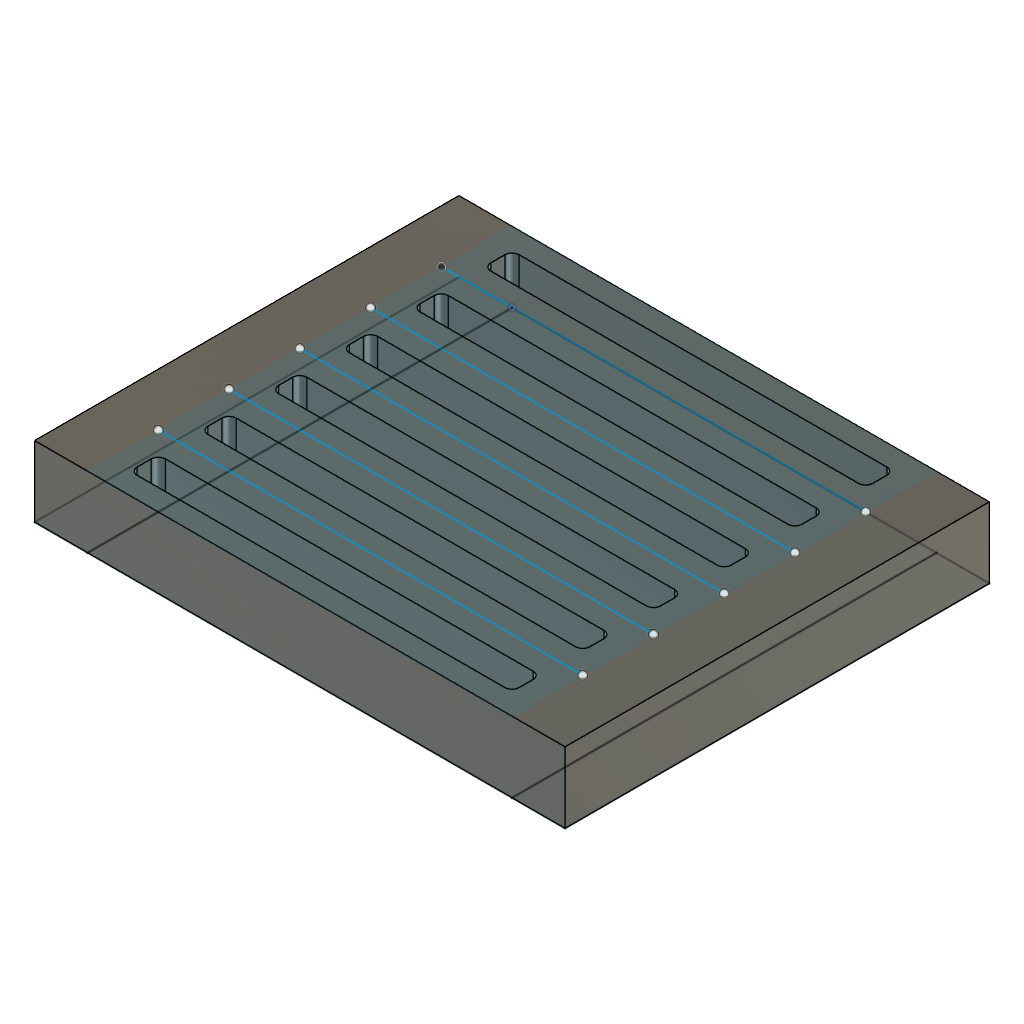
Lateral_modificado (Autodesk Fusion 360 archive; units mm, degrees)
design "Lateral_modificado"
part number: 2026-10-18-20-49-54-475
Autodesk Fusion 360 part; units mm, degrees
sketch "Boceto1" plane through (0, 0, 0) normal (0, 0, 1) x (1, 0, 0)
  line L0 (0, 0) -> (60, 0)
  line L1 (60, 0) -> (60, -60)
  line L2 (60, -60) -> (0, -60)
  line L3 (0, -60) -> (0, 0)
  line L4 (0, 0) -> (-7.5, 0)
  line L5 (-7.5, 0) -> (-7.5, -60)
  line L6 (-7.5, -60) -> (0, -60)
  line L7 (0, -60) -> (0, 0)
  line L8 (60, 0) -> (67.5, 0)
  line L9 (67.5, 0) -> (67.5, -60)
  line L10 (67.5, -60) -> (60, -60)
  line L11 (60, -60) -> (60, 0)
  dimension "d1" = 60
  dimension "d2" = 60
  dimension "d25" = 60
  dimension "d26" = 7.5
  dimension "d29" = 60
  dimension "d30" = 7.5
  constraint horizontal L0
  constraint vertical L1
  constraint horizontal L2
  constraint vertical L3
  constraint coincident L0.start L3.end
  constraint horizontal L4
  constraint vertical L5
  constraint horizontal L6
  constraint vertical L7
  constraint horizontal L8
  constraint vertical L9
  constraint horizontal L10
  constraint vertical L11
  measures "d1" distance of L0.start L0.end
  measures "d2" distance of L0.start L2.end
  measures "d25" distance of L0.start L2.end
  measures "d26" distance of L0.start L4.end
  measures "d29" distance of L0.end L1.end
  measures "d30" distance of L0.end L8.end
extrude "Extruir1" add sketch "Boceto1" along normal blind 10 contours L0 L1 L2 L3 L7 L11 makes body 1
sketch "Boceto2" plane through (0, 0, 10) normal (0, 0, 1) x (-1, 0, 0)
  line L0 (0, 60) -> (-60, 60)
  line L1 (-60, 60) -> (-60, 0)
  line L2 (-60, 0) -> (0, 0)
  line L3 (0, 0) -> (0, 60)
  line L4 (0, 10) -> (-60, 10)
  line L5 (0, 20) -> (-60, 20)
  line L6 (0, 30) -> (-60, 30)
  line L7 (0, 40) -> (-60, 40)
  line L8 (0, 50) -> (-60, 50)
  dimension "d5" = 60
  dimension "d6" = 10
  dimension "d7" = 10
  dimension "d8" = 10
  dimension "d9" = 10
  constraint coincident L3 L4.start
  constraint perpendicular L3 L4
  measures "d5" distance of L4.start L4.end
sketch "Boceto3" plane through (0, 0, 10) normal (0, 0, 1) x (-1, 0, 0)
  line L0 (0, 0) -> (-3, 0)
  line L1 (-3, 3) -> (0, 3)
  line L2 (0, 3) -> (0, 0)
  line L3 (-4, 3) -> (-56, 3)
  line L4 (-57, 4) -> (-57, 6)
  line L5 (-56, 7) -> (-4, 7)
  line L6 (-3, 6) -> (-3, 4)
  arc A0 (-4, 3) -> (-3, 4) centre (-4, 4) ccw
  arc A1 (-3, 6) -> (-4, 7) centre (-4, 6) ccw
  arc A2 (-56, 7) -> (-57, 6) centre (-56, 6) ccw
  arc A3 (-57, 4) -> (-56, 3) centre (-56, 4) ccw
  arc A4 (-3, 6) -> (-4, 7) centre (-4, 6) ccw
  line L7 (-56, 7) -> (-4, 7)
  arc A5 (-56, 7) -> (-57, 6) centre (-56, 6) ccw
  line L8 (-57, 4) -> (-57, 6)
  arc A6 (-57, 4) -> (-56, 3) centre (-56, 4) ccw
  line L9 (-4, 3) -> (-56, 3)
  arc A7 (-4, 3) -> (-3, 4) centre (-4, 4) ccw
  line L10 (-3, 6) -> (-3, 4)
  arc A8 (-3, 6) -> (-4, 7) centre (-4, 6) ccw
  line L11 (-56, 7) -> (-4, 7)
  arc A9 (-56, 7) -> (-57, 6) centre (-56, 6) ccw
  line L12 (-57, 4) -> (-57, 6)
  arc A10 (-57, 4) -> (-56, 3) centre (-56, 4) ccw
  line L13 (-4, 3) -> (-56, 3)
  arc A11 (-4, 3) -> (-3, 4) centre (-4, 4) ccw
  line L14 (-3, 6) -> (-3, 4)
  arc A12 (-3, 6) -> (-4, 7) centre (-4, 6) ccw
  line L15 (-56, 7) -> (-4, 7)
  arc A13 (-56, 7) -> (-57, 6) centre (-56, 6) ccw
  line L16 (-57, 4) -> (-57, 6)
  arc A14 (-57, 4) -> (-56, 3) centre (-56, 4) ccw
  line L17 (-4, 3) -> (-56, 3)
  arc A15 (-4, 3) -> (-3, 4) centre (-4, 4) ccw
  line L18 (-3, 6) -> (-3, 4)
  line L19 (0, 10) -> (-60, 10)
  line L20 (-56, 13) -> (-4, 13)
  line L21 (-56, 13) -> (-4, 13)
  line L22 (-56, 13) -> (-4, 13)
  line L23 (-56, 13) -> (-4, 13)
  arc A16 (-4, 13) -> (-3, 14) centre (-4, 14) ccw
  line L24 (-3, 14) -> (-3, 16)
  line L25 (-3, 14) -> (-3, 16)
  arc A17 (-4, 13) -> (-3, 14) centre (-4, 14) ccw
  line L26 (-3, 14) -> (-3, 16)
  arc A18 (-4, 13) -> (-3, 14) centre (-4, 14) ccw
  line L27 (-3, 14) -> (-3, 16)
  arc A19 (-4, 13) -> (-3, 14) centre (-4, 14) ccw
  arc A20 (-3, 16) -> (-4, 17) centre (-4, 16) ccw
  arc A21 (-3, 16) -> (-4, 17) centre (-4, 16) ccw
  arc A22 (-3, 16) -> (-4, 17) centre (-4, 16) ccw
  arc A23 (-3, 16) -> (-4, 17) centre (-4, 16) ccw
  line L28 (-57, 16) -> (-57, 14)
  arc A24 (-57, 14) -> (-56, 13) centre (-56, 14) ccw
  arc A25 (-56, 17) -> (-57, 16) centre (-56, 16) ccw
  arc A26 (-57, 14) -> (-56, 13) centre (-56, 14) ccw
  arc A27 (-57, 14) -> (-56, 13) centre (-56, 14) ccw
  line L29 (-57, 16) -> (-57, 14)
  arc A28 (-56, 17) -> (-57, 16) centre (-56, 16) ccw
  arc A29 (-57, 14) -> (-56, 13) centre (-56, 14) ccw
  arc A30 (-56, 17) -> (-57, 16) centre (-56, 16) ccw
  line L30 (-57, 16) -> (-57, 14)
  arc A31 (-56, 17) -> (-57, 16) centre (-56, 16) ccw
  line L31 (-57, 16) -> (-57, 14)
  line L32 (-4, 17) -> (-56, 17)
  line L33 (0, 20) -> (-60, 20)
  line L34 (-57, 36) -> (-57, 34)
  line L35 (-3, 34) -> (-3, 36)
  line L36 (-4, 37) -> (-56, 37)
  arc A32 (-57, 34) -> (-56, 33) centre (-56, 34) ccw
  arc A33 (-4, 33) -> (-3, 34) centre (-4, 34) ccw
  arc A34 (-56, 37) -> (-57, 36) centre (-56, 36) ccw
  arc A35 (-4, 33) -> (-3, 34) centre (-4, 34) ccw
  arc A36 (-56, 37) -> (-57, 36) centre (-56, 36) ccw
  arc A37 (-56, 37) -> (-57, 36) centre (-56, 36) ccw
  arc A38 (-3, 36) -> (-4, 37) centre (-4, 36) ccw
  line L37 (-56, 33) -> (-4, 33)
  arc A39 (-4, 33) -> (-3, 34) centre (-4, 34) ccw
  arc A40 (-4, 33) -> (-3, 34) centre (-4, 34) ccw
  line L38 (-4, 37) -> (-56, 37)
  arc A41 (-57, 34) -> (-56, 33) centre (-56, 34) ccw
  arc A42 (-3, 36) -> (-4, 37) centre (-4, 36) ccw
  line L39 (-3, 34) -> (-3, 36)
  line L40 (-4, 37) -> (-56, 37)
  line L41 (-3, 34) -> (-3, 36)
  line L42 (-3, 34) -> (-3, 36)
  arc A43 (-57, 34) -> (-56, 33) centre (-56, 34) ccw
  line L43 (-56, 33) -> (-4, 33)
  line L44 (-57, 36) -> (-57, 34)
  arc A44 (-56, 37) -> (-57, 36) centre (-56, 36) ccw
  line L45 (-56, 33) -> (-4, 33)
  line L46 (-4, 37) -> (-56, 37)
  line L47 (-57, 36) -> (-57, 34)
  arc A45 (-3, 36) -> (-4, 37) centre (-4, 36) ccw
  line L48 (-56, 33) -> (-4, 33)
  arc A46 (-3, 36) -> (-4, 37) centre (-4, 36) ccw
  line L49 (-57, 36) -> (-57, 34)
  arc A47 (-57, 34) -> (-56, 33) centre (-56, 34) ccw
  line L50 (-56, 33) -> (-4, 33)
  line L51 (-56, 33) -> (-4, 33)
  arc A48 (-56, 37) -> (-57, 36) centre (-56, 36) ccw
  line L52 (-4, 37) -> (-56, 37)
  arc A49 (-3, 36) -> (-4, 37) centre (-4, 36) ccw
  line L53 (-57, 36) -> (-57, 34)
  arc A50 (-56, 37) -> (-57, 36) centre (-56, 36) ccw
  arc A51 (-4, 33) -> (-3, 34) centre (-4, 34) ccw
  arc A52 (-57, 34) -> (-56, 33) centre (-56, 34) ccw
  line L54 (-4, 37) -> (-56, 37)
  arc A53 (-4, 33) -> (-3, 34) centre (-4, 34) ccw
  line L55 (-3, 34) -> (-3, 36)
  line L56 (-3, 34) -> (-3, 36)
  arc A54 (-4, 33) -> (-3, 34) centre (-4, 34) ccw
  arc A55 (-3, 36) -> (-4, 37) centre (-4, 36) ccw
  line L57 (-56, 33) -> (-4, 33)
  arc A56 (-4, 33) -> (-3, 34) centre (-4, 34) ccw
  line L58 (-56, 33) -> (-4, 33)
  line L59 (-57, 36) -> (-57, 34)
  arc A57 (-57, 34) -> (-56, 33) centre (-56, 34) ccw
  arc A58 (-57, 34) -> (-56, 33) centre (-56, 34) ccw
  line L60 (-57, 36) -> (-57, 34)
  arc A59 (-56, 37) -> (-57, 36) centre (-56, 36) ccw
  line L61 (-3, 34) -> (-3, 36)
  line L62 (-4, 37) -> (-56, 37)
  line L63 (-3, 34) -> (-3, 36)
  arc A60 (-56, 37) -> (-57, 36) centre (-56, 36) ccw
  line L64 (-57, 36) -> (-57, 34)
  arc A61 (-57, 34) -> (-56, 33) centre (-56, 34) ccw
  arc A62 (-3, 36) -> (-4, 37) centre (-4, 36) ccw
  arc A63 (-3, 36) -> (-4, 37) centre (-4, 36) ccw
  line L65 (-4, 37) -> (-56, 37)
  line L66 (-3, 26) -> (-3, 24)
  arc A64 (-4, 23) -> (-3, 24) centre (-4, 24) ccw
  arc A65 (-3, 26) -> (-4, 27) centre (-4, 26) ccw
  line L67 (-57, 24) -> (-57, 26)
  arc A66 (-56, 27) -> (-57, 26) centre (-56, 26) ccw
  arc A67 (-56, 27) -> (-57, 26) centre (-56, 26) ccw
  arc A68 (-4, 23) -> (-3, 24) centre (-4, 24) ccw
  arc A69 (-3, 26) -> (-4, 27) centre (-4, 26) ccw
  arc A70 (-3, 26) -> (-4, 27) centre (-4, 26) ccw
  arc A71 (-4, 23) -> (-3, 24) centre (-4, 24) ccw
  arc A72 (-57, 24) -> (-56, 23) centre (-56, 24) ccw
  line L68 (-3, 26) -> (-3, 24)
  line L69 (-57, 24) -> (-57, 26)
  arc A73 (-56, 27) -> (-57, 26) centre (-56, 26) ccw
  arc A74 (-57, 24) -> (-56, 23) centre (-56, 24) ccw
  arc A75 (-56, 27) -> (-57, 26) centre (-56, 26) ccw
  arc A76 (-4, 23) -> (-3, 24) centre (-4, 24) ccw
  line L70 (-57, 24) -> (-57, 26)
  line L71 (-3, 26) -> (-3, 24)
  line L72 (-56, 27) -> (-4, 27)
  arc A77 (-57, 24) -> (-56, 23) centre (-56, 24) ccw
  line L73 (-56, 27) -> (-4, 27)
  line L74 (-4, 23) -> (-56, 23)
  arc A78 (-3, 26) -> (-4, 27) centre (-4, 26) ccw
  line L75 (-3, 26) -> (-3, 24)
  line L76 (-56, 27) -> (-4, 27)
  arc A79 (-57, 24) -> (-56, 23) centre (-56, 24) ccw
  line L77 (-57, 24) -> (-57, 26)
  line L78 (-56, 27) -> (-4, 27)
  line L79 (0, 40) -> (-60, 40)
  line L80 (-57, 44) -> (-57, 46)
  arc A80 (-3, 46) -> (-4, 47) centre (-4, 46) ccw
  arc A81 (-3, 46) -> (-4, 47) centre (-4, 46) ccw
  line L81 (-57, 44) -> (-57, 46)
  arc A82 (-3, 46) -> (-4, 47) centre (-4, 46) ccw
  line L82 (-57, 44) -> (-57, 46)
  arc A83 (-4, 43) -> (-3, 44) centre (-4, 44) ccw
  arc A84 (-4, 43) -> (-3, 44) centre (-4, 44) ccw
  line L83 (-57, 44) -> (-57, 46)
  arc A85 (-4, 43) -> (-3, 44) centre (-4, 44) ccw
  arc A86 (-3, 46) -> (-4, 47) centre (-4, 46) ccw
  arc A87 (-4, 43) -> (-3, 44) centre (-4, 44) ccw
  line L84 (-57, 44) -> (-57, 46)
  arc A88 (-3, 46) -> (-4, 47) centre (-4, 46) ccw
  arc A89 (-3, 46) -> (-4, 47) centre (-4, 46) ccw
  arc A90 (-4, 43) -> (-3, 44) centre (-4, 44) ccw
  arc A91 (-4, 43) -> (-3, 44) centre (-4, 44) ccw
  line L85 (-57, 44) -> (-57, 46)
  line L86 (-57, 44) -> (-57, 46)
  line L87 (-57, 44) -> (-57, 46)
  arc A92 (-4, 43) -> (-3, 44) centre (-4, 44) ccw
  arc A93 (-56, 47) -> (-57, 46) centre (-56, 46) ccw
  arc A94 (-57, 44) -> (-56, 43) centre (-56, 44) ccw
  arc A95 (-57, 44) -> (-56, 43) centre (-56, 44) ccw
  arc A96 (-56, 47) -> (-57, 46) centre (-56, 46) ccw
  arc A97 (-57, 44) -> (-56, 43) centre (-56, 44) ccw
  arc A98 (-56, 47) -> (-57, 46) centre (-56, 46) ccw
  arc A99 (-57, 44) -> (-56, 43) centre (-56, 44) ccw
  arc A100 (-56, 47) -> (-57, 46) centre (-56, 46) ccw
  arc A101 (-56, 47) -> (-57, 46) centre (-56, 46) ccw
  line L88 (-56, 47) -> (-4, 47)
  line L89 (-4, 43) -> (-56, 43)
  arc A102 (-4, 43) -> (-3, 44) centre (-4, 44) ccw
  line L90 (-3, 46) -> (-3, 44)
  line L91 (-4, 43) -> (-56, 43)
  line L92 (-56, 47) -> (-4, 47)
  line L93 (-4, 43) -> (-56, 43)
  line L94 (-3, 46) -> (-3, 44)
  line L95 (-56, 47) -> (-4, 47)
  line L96 (-56, 47) -> (-4, 47)
  line L97 (-56, 47) -> (-4, 47)
  line L98 (-3, 46) -> (-3, 44)
  line L99 (-4, 43) -> (-56, 43)
  line L100 (-56, 47) -> (-4, 47)
  line L101 (-56, 47) -> (-4, 47)
  line L102 (-4, 43) -> (-56, 43)
  line L103 (-3, 46) -> (-3, 44)
  line L104 (-4, 43) -> (-56, 43)
  arc A103 (-3, 46) -> (-4, 47) centre (-4, 46) ccw
  arc A104 (-3, 46) -> (-4, 47) centre (-4, 46) ccw
  line L105 (-3, 46) -> (-3, 44)
  line L106 (-3, 46) -> (-3, 44)
  line L107 (-56, 47) -> (-4, 47)
  line L108 (-4, 43) -> (-56, 43)
  line L109 (-3, 46) -> (-3, 44)
  line L110 (-3, 46) -> (-3, 44)
  line L111 (-4, 43) -> (-56, 43)
  arc A105 (-56, 47) -> (-57, 46) centre (-56, 46) ccw
  arc A106 (-57, 44) -> (-56, 43) centre (-56, 44) ccw
  arc A107 (-57, 44) -> (-56, 43) centre (-56, 44) ccw
  arc A108 (-56, 47) -> (-57, 46) centre (-56, 46) ccw
  arc A109 (-57, 44) -> (-56, 43) centre (-56, 44) ccw
  arc A110 (-57, 44) -> (-56, 43) centre (-56, 44) ccw
  arc A111 (-56, 47) -> (-57, 46) centre (-56, 46) ccw
  line L112 (0, 50) -> (-60, 50)
  line L113 (-3, 54) -> (-3, 56)
  line L114 (-57, 56) -> (-57, 54)
  line L115 (-57, 56) -> (-57, 54)
  line L116 (-3, 54) -> (-3, 56)
  line L117 (-57, 56) -> (-57, 54)
  line L118 (-3, 54) -> (-3, 56)
  line L119 (-57, 56) -> (-57, 54)
  line L120 (-3, 54) -> (-3, 56)
  line L121 (-3, 54) -> (-3, 56)
  line L122 (-3, 54) -> (-3, 56)
  line L123 (-3, 54) -> (-3, 56)
  line L124 (-3, 54) -> (-3, 56)
  line L125 (-56, 53) -> (-4, 53)
  arc A112 (-56, 57) -> (-57, 56) centre (-56, 56) ccw
  line L126 (-4, 57) -> (-56, 57)
  line L127 (-4, 57) -> (-56, 57)
  line L128 (-4, 57) -> (-56, 57)
  arc A113 (-56, 57) -> (-57, 56) centre (-56, 56) ccw
  line L129 (-4, 57) -> (-56, 57)
  line L130 (-56, 53) -> (-4, 53)
  line L131 (-56, 53) -> (-4, 53)
  arc A114 (-56, 57) -> (-57, 56) centre (-56, 56) ccw
  arc A115 (-56, 57) -> (-57, 56) centre (-56, 56) ccw
  line L132 (-56, 53) -> (-4, 53)
  arc A116 (-57, 54) -> (-56, 53) centre (-56, 54) ccw
  arc A117 (-57, 54) -> (-56, 53) centre (-56, 54) ccw
  arc A118 (-57, 54) -> (-56, 53) centre (-56, 54) ccw
  arc A119 (-57, 54) -> (-56, 53) centre (-56, 54) ccw
  arc A120 (-56, 57) -> (-57, 56) centre (-56, 56) ccw
  arc A121 (-57, 54) -> (-56, 53) centre (-56, 54) ccw
  line L133 (-4, 57) -> (-56, 57)
  line L134 (-4, 57) -> (-56, 57)
  arc A122 (-57, 54) -> (-56, 53) centre (-56, 54) ccw
  arc A123 (-4, 53) -> (-3, 54) centre (-4, 54) ccw
  arc A124 (-4, 53) -> (-3, 54) centre (-4, 54) ccw
  line L135 (-4, 57) -> (-56, 57)
  arc A125 (-3, 56) -> (-4, 57) centre (-4, 56) ccw
  arc A126 (-3, 56) -> (-4, 57) centre (-4, 56) ccw
  arc A127 (-4, 53) -> (-3, 54) centre (-4, 54) ccw
  line L136 (-56, 53) -> (-4, 53)
  arc A128 (-57, 54) -> (-56, 53) centre (-56, 54) ccw
  line L137 (-56, 53) -> (-4, 53)
  line L138 (-57, 56) -> (-57, 54)
  arc A129 (-3, 56) -> (-4, 57) centre (-4, 56) ccw
  arc A130 (-4, 53) -> (-3, 54) centre (-4, 54) ccw
  arc A131 (-3, 56) -> (-4, 57) centre (-4, 56) ccw
  arc A132 (-4, 53) -> (-3, 54) centre (-4, 54) ccw
  line L139 (-57, 56) -> (-57, 54)
  arc A133 (-4, 53) -> (-3, 54) centre (-4, 54) ccw
  arc A134 (-56, 57) -> (-57, 56) centre (-56, 56) ccw
  arc A135 (-3, 56) -> (-4, 57) centre (-4, 56) ccw
  line L140 (-57, 56) -> (-57, 54)
  arc A136 (-4, 53) -> (-3, 54) centre (-4, 54) ccw
  arc A137 (-4, 53) -> (-3, 54) centre (-4, 54) ccw
  line L141 (-56, 53) -> (-4, 53)
  line L142 (-4, 57) -> (-56, 57)
  line L143 (-57, 56) -> (-57, 54)
  arc A138 (-3, 56) -> (-4, 57) centre (-4, 56) ccw
  arc A139 (-3, 56) -> (-4, 57) centre (-4, 56) ccw
  arc A140 (-3, 56) -> (-4, 57) centre (-4, 56) ccw
  arc A141 (-56, 57) -> (-57, 56) centre (-56, 56) ccw
  arc A142 (-56, 57) -> (-57, 56) centre (-56, 56) ccw
  arc A143 (-57, 54) -> (-56, 53) centre (-56, 54) ccw
  line L144 (-56, 53) -> (-4, 53)
  point P0 (-57, 3)
  point P1 (-3, 7)
  point P2 (-3, 13)
  point P3 (-3, 17)
  point P4 (-57, 17)
  point P5 (-57, 37)
  point P6 (-3, 37)
  point P7 (-3, 33)
  point P8 (-3, 37)
  point P9 (-3, 33)
  point P10 (-57, 37)
  point P11 (-57, 23)
  point P12 (-3, 23)
  point P13 (-3, 27)
  point P14 (-57, 43)
  point P15 (-3, 47)
  point P16 (-3, 47)
  point P17 (-57, 43)
  point P18 (-3, 43)
  point P19 (-3, 43)
  point P20 (-3, 53)
  point P21 (-57, 57)
  point P22 (-57, 57)
  point P23 (-3, 57)
  point P24 (-3, 53)
  point P25 (-3, 57)
  dimension "d10" = 3
  dimension "d11" = 3
  dimension "d12" = 54
  dimension "d13" = 4
  dimension "d14" = 1
  dimension "d15" = 1
  dimension "d16" = 1
  dimension "d17" = 1
  dimension "d18" = 0
  dimension "d19" = 0
  dimension "d20" = 0
  constraint horizontal L0
  constraint horizontal L1
  constraint vertical L2
  constraint coincident L0.start L2.end
  constraint horizontal L3
  constraint vertical L4
  constraint horizontal L5
  constraint vertical L6
  constraint coincident L1.start L3
  constraint coincident L1.start L6
  constraint tangent L3 A0
  constraint tangent L6 A0
  constraint coincident P1 L6
  constraint coincident P1 L5
  constraint tangent L6 A1
  constraint tangent L5 A1
  constraint tangent L5 A2
  constraint tangent L4 A2
  constraint coincident P0 L3
  constraint coincident P0 L4
  constraint tangent L3 A3
  constraint tangent L4 A3
  constraint symmetric L1.start L19 P3
  constraint symmetric P0 L19 P4
  constraint symmetric P1 L19 P2
  constraint symmetric L3.start L19 A20.end
  constraint symmetric L6.end L19 L24.end
  constraint symmetric A0 L19 A22
  constraint symmetric L6.start L19 A16.end
  constraint symmetric L5.end L19 L20.end
  constraint symmetric A1 L19 A16
  constraint symmetric L5.start L19 L20.start
  constraint symmetric L4.end L19 L28.end
  constraint symmetric A2 L19 A26
  constraint symmetric L3.end L19 A25.start
  constraint symmetric L4.start L19 L28.start
  constraint symmetric A3 L19 A25
  constraint symmetric A4 L19 A19
  constraint symmetric A5 L19 A27
  constraint symmetric A6 L19 A30
  constraint symmetric A7 L19 A23
  constraint symmetric A8 L19 A17
  constraint symmetric A9 L19 A24
  constraint symmetric A10 L19 A31
  constraint symmetric A11 L19 A20
  constraint symmetric A12 L19 A18
  constraint symmetric A13 L19 A29
  constraint symmetric A14 L19 A28
  constraint symmetric A15 L19 A21
  constraint symmetric L1.start L33 P8
  constraint symmetric P0 L33 P10
  constraint symmetric P1 L33 P9
  constraint symmetric L3.start L33 L36.start
  constraint symmetric L6.end L33 L35.end
  constraint symmetric A0 L33 A46
  constraint symmetric L6.start L33 L35.start
  constraint symmetric L5.end L33 A33.start
  constraint symmetric A1 L33 A33
  constraint symmetric L5.start L33 A32.end
  constraint symmetric L4.end L33 L34.end
  constraint symmetric A2 L33 A43
  constraint symmetric L3.end L33 L36.end
  constraint symmetric L4.start L33 L34.start
  constraint symmetric A3 L33 A36
  constraint symmetric A4 L33 A39
  constraint symmetric A5 L33 A47
  constraint symmetric A6 L33 A34
  constraint symmetric A7 L33 A42
  constraint symmetric A8 L33 A35
  constraint symmetric A9 L33 A32
  constraint symmetric A10 L33 A44
  constraint symmetric A11 L33 A45
  constraint symmetric A12 L33 A40
  constraint symmetric A13 L33 A41
  constraint symmetric A14 L33 A37
  constraint symmetric A15 L33 A38
  constraint symmetric A0 L33 A49
  constraint symmetric A1 L33 A51
  constraint symmetric A2 L33 A52
  constraint symmetric A3 L33 A60
  constraint symmetric A4 L33 A54
  constraint symmetric A5 L33 A61
  constraint symmetric A6 L33 A50
  constraint symmetric A7 L33 A55
  constraint symmetric A8 L33 A53
  constraint symmetric A9 L33 A58
  constraint symmetric A10 L33 A48
  constraint symmetric A11 L33 A63
  constraint symmetric A12 L33 A56
  constraint symmetric A13 L33 A57
  constraint symmetric A14 L33 A59
  constraint symmetric A15 L33 A62
  constraint symmetric A16.end L33 L66.start
  constraint symmetric P2 L33 P13
  constraint symmetric P3 L33 P12
  constraint symmetric A25.start L33 A72.end
  constraint symmetric L28.end L33 L67.end
  constraint symmetric L28.start L33 L67.start
  constraint symmetric L20.start L33 A66.start
  constraint symmetric P4 L33 P11
  constraint symmetric L20.end L33 A65.end
  constraint symmetric A16 L33 A78
  constraint symmetric L24.end L33 L66.end
  constraint symmetric A17 L33 A70
  constraint symmetric A18 L33 A65
  constraint symmetric A19 L33 A69
  constraint symmetric A20.end L33 A64.start
  constraint symmetric A20 L33 A71
  constraint symmetric A21 L33 A64
  constraint symmetric A22 L33 A76
  constraint symmetric A23 L33 A68
  constraint symmetric A24 L33 A67
  constraint symmetric A25 L33 A72
  constraint symmetric A26 L33 A66
  constraint symmetric A27 L33 A73
  constraint symmetric A28 L33 A79
  constraint symmetric A29 L33 A75
  constraint symmetric A30 L33 A74
  constraint symmetric A31 L33 A77
  constraint symmetric L34.end L79 L80.end
  constraint symmetric L36.end L79 A94.end
  constraint symmetric A32.end L79 A93.start
  constraint symmetric L34.start L79 L80.start
  constraint symmetric P10 L79 P17
  constraint symmetric A33.start L79 A80.end
  constraint symmetric L35.start L79 A80.start
  constraint symmetric L36.start L79 A83.start
  constraint symmetric L35.end L79 A83.end
  constraint symmetric P8 L79 P19
  constraint symmetric P9 L79 P16
  constraint symmetric A32 L79 A108
  constraint symmetric A33 L79 A80
  constraint symmetric A34 L79 A97
  constraint symmetric A35 L79 A103
  constraint symmetric A36 L79 A110
  constraint symmetric A37 L79 A107
  constraint symmetric A38 L79 A87
  constraint symmetric A39 L79 A81
  constraint symmetric A40 L79 A86
  constraint symmetric A41 L79 A96
  constraint symmetric A42 L79 A92
  constraint symmetric A43 L79 A98
  constraint symmetric A44 L79 A94
  constraint symmetric A45 L79 A90
  constraint symmetric A46 L79 A102
  constraint symmetric A47 L79 A111
  constraint symmetric A48 L79 A95
  constraint symmetric A49 L79 A91
  constraint symmetric A50 L79 A99
  constraint symmetric A51 L79 A88
  constraint symmetric A52 L79 A105
  constraint symmetric A53 L79 A104
  constraint symmetric A54 L79 A82
  constraint symmetric A55 L79 A83
  constraint symmetric A56 L79 A89
  constraint symmetric A57 L79 A101
  constraint symmetric A58 L79 A93
  constraint symmetric A59 L79 A109
  constraint symmetric A60 L79 A106
  constraint symmetric A61 L79 A100
  constraint symmetric A62 L79 A84
  constraint symmetric A63 L79 A85
  constraint symmetric A80.end L112 L125.end
  constraint symmetric A83.start L112 L126.start
  constraint symmetric A80.start L112 L113.start
  constraint symmetric A93.start L112 L125.start
  constraint symmetric L80.end L112 L114.end
  constraint symmetric A94.end L112 A112.start
  constraint symmetric L80.start L112 L114.start
  constraint symmetric P17 L112 P22
  constraint symmetric A83.end L112 L113.end
  constraint symmetric P16 L112 P24
  constraint symmetric P19 L112 P25
  constraint symmetric A80 L112 A123
  constraint symmetric A81 L112 A132
  constraint symmetric A82 L112 A137
  constraint symmetric A83 L112 A125
  constraint symmetric A84 L112 A139
  constraint symmetric A85 L112 A138
  constraint symmetric A86 L112 A127
  constraint symmetric A87 L112 A140
  constraint symmetric A88 L112 A124
  constraint symmetric A89 L112 A133
  constraint symmetric A90 L112 A126
  constraint symmetric A91 L112 A135
  constraint symmetric A92 L112 A131
  constraint symmetric A93 L112 A128
  constraint symmetric A94 L112 A113
  constraint symmetric A95 L112 A112
  constraint symmetric A96 L112 A143
  constraint symmetric A97 L112 A120
  constraint symmetric A98 L112 A122
  constraint symmetric A99 L112 A114
  constraint symmetric A100 L112 A121
  constraint symmetric A101 L112 A117
  constraint symmetric A102 L112 A129
  constraint symmetric A103 L112 A130
  constraint symmetric A104 L112 A136
  constraint symmetric A105 L112 A118
  constraint symmetric A106 L112 A141
  constraint symmetric A107 L112 A142
  constraint symmetric A108 L112 A116
  constraint symmetric A109 L112 A115
  constraint symmetric A110 L112 A134
  constraint symmetric A111 L112 A119
  measures "d10" distance of L0.start L0.end
  measures "d11" distance of L0.start L1.end
  measures "d12" distance of L1.start P0
  measures "d13" distance of L1.start P1
  measures "d14" radius of A0
  measures "d15" radius of A1
  measures "d16" radius of A2
  measures "d17" radius of A3
  measures "d18" distance of L5
  measures "d19" distance of L7
  measures "d20" distance of L7
ref_plane "PlanoDeObra1" through (30, -10, 5) normal (0, 1, 0) x (-1, 0, 0)
extrude "Extruir2" cut sketch "Boceto3" against normal blind 10 bodies 1
sketch "Boceto4" plane through (0, 0, 10) normal (0, 0, 1) x (-1, 0, 0)
extrude "Extruir3" add sketch "Boceto1" along normal blind 10 separate body contours L3 L4 L5 L6 L7 makes body 2
combine "Combinar1" operation add target body 2 tool bodies 1
extrude "Extruir4" add sketch "Boceto1" along normal blind 10 separate body contours L1 L8 L9 L10 L11 makes body 3
combine "Combinar2" operation add target body 3 tool bodies 2
equation "d20 = -d19"
